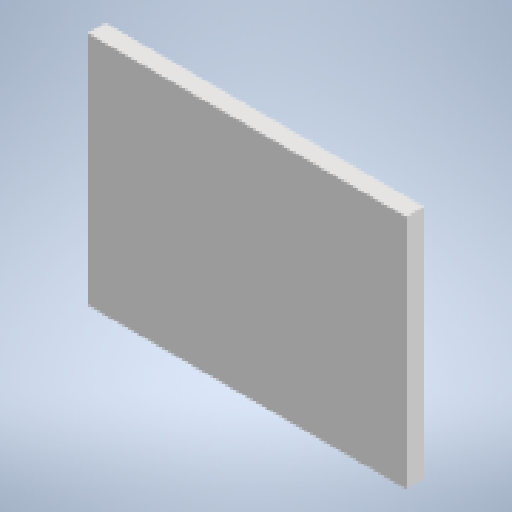
# Autodesk Inventor part: ноутбук
Saved by Autodesk Inventor 2024.2 (Build 282272000, 272)
## iProperties
Created: 2026-10-08
Part Number: ноутбук
Material: Типовые
Document SubType Name: Modeling
Designer: User
Density: 1 g/cm^3
Appearance: По умолчанию
Author: User
Autodesk Inventor part; units mm, degrees
ref_plane "YZ Plane" through (0, 0, 0) normal (1, 0, 0) x (0, 1, 0)
ref_plane "XZ Plane" through (0, 0, 0) normal (0, 1, 0) x (-1, 0, 0)
ref_plane "XY Plane" through (0, 0, 0) normal (0, 0, 1) x (1, 0, 0)
sketch "Эскиз1" plane through (0, 0, 0) normal (0, 0, 1) x (1, 0, 0)
  line L0 (160.2228, 497.186) -> (-196.7772, 497.186)
  line L1 (-196.7772, 497.186) -> (-196.7772, 233.186)
  line L2 (-196.7772, 233.186) -> (160.2228, 233.186)
  line L3 (160.2228, 233.186) -> (160.2228, 497.186)
  point P0 (0, 0)
  dimension "d0" = 357
  dimension "d1" = 264
  constraints: 8 end point, 2 parallel, 1 horizontal, 1 perpendicular
  measures "d0" distance of L0.start L0.end
  measures "d1" distance of L2.end L0.start
extrude "Выдавливание1" add sketch "Эскиз1" along normal blind 20
